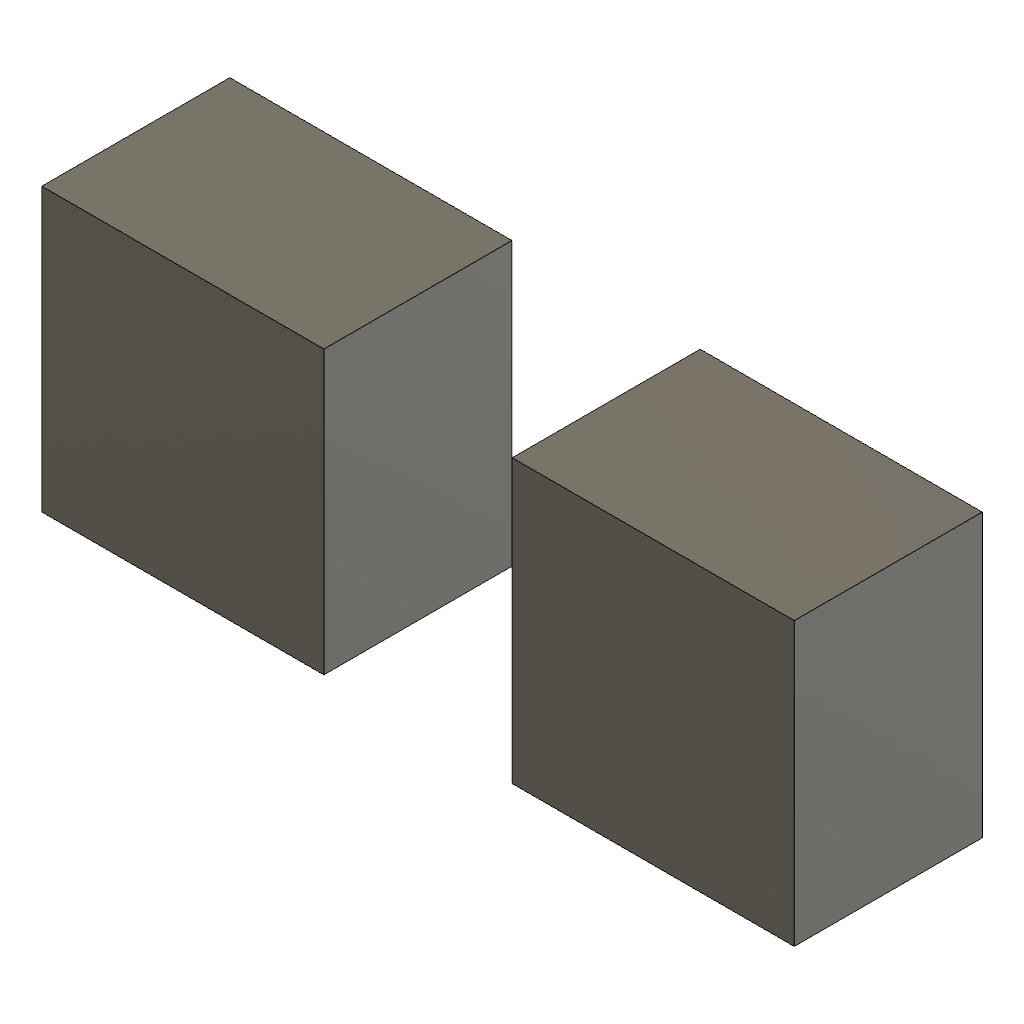
feature_identical (Autodesk Fusion 360 design; units mm, degrees)
part number: 2026-10-20-23-40-47-145
Autodesk Fusion 360 part; units mm, degrees
sketch "MirrorSeedSketch" plane through (0, 0, 0) normal (0, 0, 1) x (1, 0, 0)
  line L0 (10, 10) -> (40, 10)
  line L1 (40, 10) -> (40, 40)
  line L2 (40, 40) -> (10, 40)
  line L3 (10, 40) -> (10, 10)
extrude "MirrorSeedExtrude" add sketch "MirrorSeedSketch" along normal blind 20 makes body 1
mirror "ProbeMirrorFeatureModes" about plane through (0, 0, 0) normal (1, 0, 0) of "MirrorSeedExtrude" makes body 2
named bodies: "MirrorSeedBody", "MirrorSeedBody (1)"
